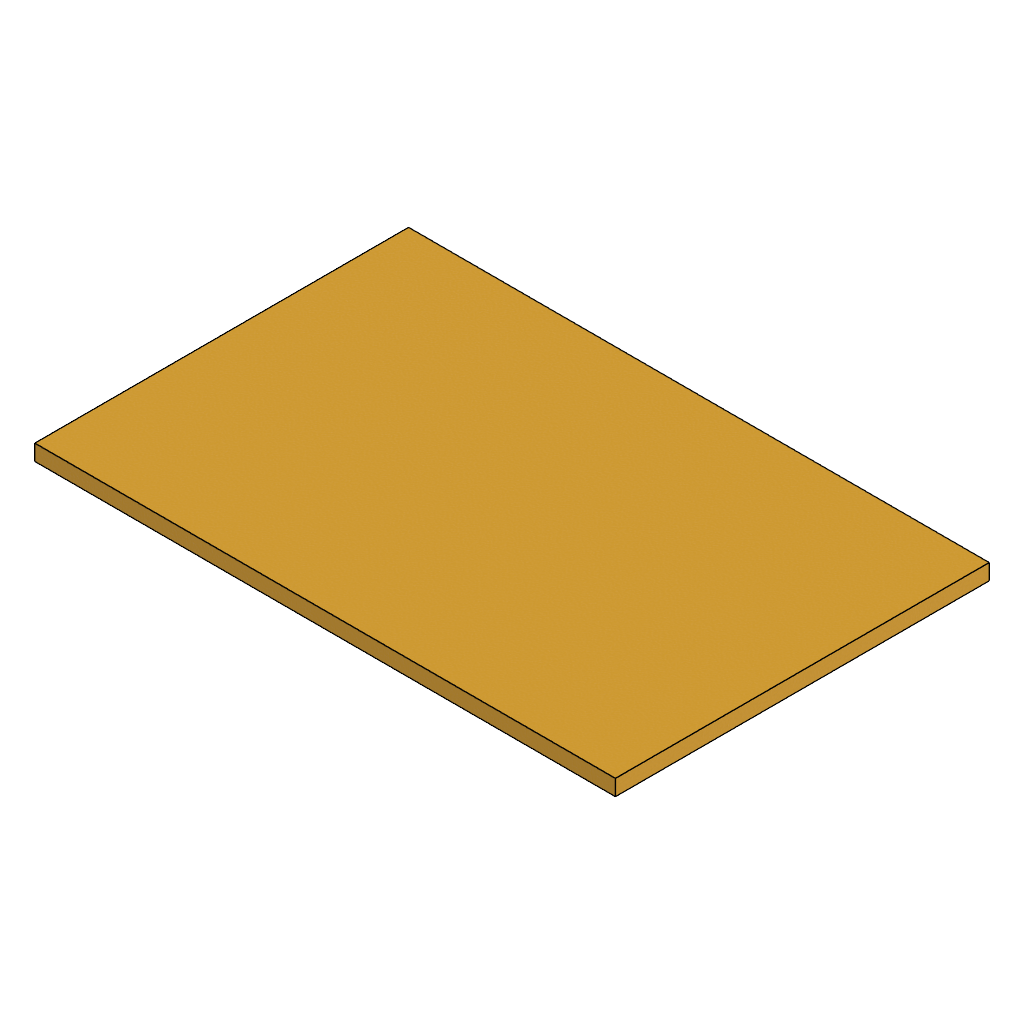
00-27 Perfboard Arduino Nano support Placeholder (Autodesk Fusion 360 design; units mm, degrees)
part number: 2026-11-10-14-12-37-198
Autodesk Fusion 360 part; units mm, degrees
sketch "Sketch1" plane through (0, 0, 0) normal (0, 0, 1) x (1, 0, 0)
  line L0 (0, 0) -> (73, 0)
  line L1 (73, 0) -> (73, 47)
  line L2 (73, 47) -> (0, 47)
  line L3 (0, 47) -> (0, 0)
  dimension "d1" = 47
  dimension "d2" = 73
  constraint horizontal L0
  constraint vertical L1
  constraint horizontal L2
  constraint vertical L3
  constraint coincident L0.start L3.end
  measures "d1" distance of L0.start L2.end
  measures "d2" distance of L1.end L2.end
extrude "Extrude1" add sketch "Sketch1" along normal blind 2
